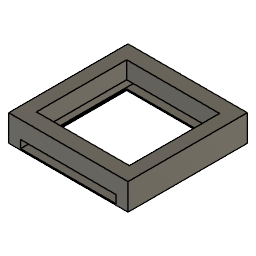
ELASTOMER HOUSING (Autodesk Fusion 360 design; units mm, degrees)
Autodesk Fusion 360 part; units mm, degrees
sketch "Sketch1" plane through (0, 0, 0) normal (0, 1, 0) x (1, 0, 0)
  line L0 (0, 0) -> (45, 0)
  line L1 (45, 0) -> (45, -10)
  line L2 (45, -10) -> (0, -10)
  line L3 (0, -10) -> (0, 0)
  line L4 (0, 0) -> (0, -2)
  line L5 (40.5, -3.5) -> (4.5, -3.5)
  line L6 (4.5, -3.5) -> (4.5, -0.5)
  line L7 (4.5, -0.5) -> (40.5, -0.5)
  line L8 (40.5, -0.5) -> (40.5, -3.5)
  dimension "d1" = 45
  dimension "d2" = 10
  dimension "d3" = 36
  dimension "d4" = 3
  constraint horizontal L0
  constraint vertical L1
  constraint horizontal L2
  constraint vertical L3
  constraint coincident L0.start L3.end
  constraint coincident L3 L4.end
  constraint horizontal L5
  constraint perpendicular L5 L6
  constraint parallel L5 L7
  constraint parallel L6 L8
  measures "d1" distance of L0.start L0.end
  measures "d2" distance of L0.start L2.end
  measures "d3" distance of L6.end L7.end
  measures "d4" distance of L5.end L6.end
extrude "Extrude1" add sketch "Sketch1" along normal blind 45
sketch "Sketch2" plane through (0, 0, 0.5) normal (0, 0, 1) x (-1, 0, 0)
  line L0 (-4.5, 0) -> (-40.5, 0)
  line L1 (-40.5, 0) -> (-40.5, -45)
  line L2 (-40.5, -45) -> (-4.5, -45)
  line L3 (-4.5, -45) -> (-4.5, 0)
  line L4 (-40, -44.5) -> (-5, -44.5)
  line L5 (-5, -44.5) -> (-5, -0.5)
  line L6 (-5, -0.5) -> (-40, -0.5)
  line L7 (-40, -0.5) -> (-40, -44.5)
  dimension "d7" = -0.5
extrude "Extrude2" cut sketch "Sketch2" against normal blind 8.5 contours L4 L5 L6 L7
extrude "Extrude3" add 1 faces at (28.3333, 44.5, 0.3333) along direction (0, -1, 0) blind 5
extrude "Extrude4" add 1 faces at (16.6667, 0.5, 0.3333) along direction (0, 1, 0) blind 5
sketch "Sketch3" plane through (0, 0, 0.5) normal (0, 0, 1) x (-1, 0, 0)
  line L0 (-40, -5.5) -> (-5, -5.5)
  line L1 (-5, -5.5) -> (-5, -39.5)
  line L2 (-5, -39.5) -> (-40, -39.5)
  line L3 (-40, -39.5) -> (-40, -5.5)
  constraint horizontal L0
  constraint vertical L1
  constraint horizontal L2
  constraint vertical L3
extrude "Extrude5" cut sketch "Sketch2" along normal blind 36 contours L4 L5 L6 L7
extrude "Extrude6" add 1 faces at (28.3333, 44.5, 5.6667) along direction (0, -1, 0) blind 6
extrude "Extrude7" add 1 faces at (16.6667, 0.5, 5.6667) along direction (0, 1, 0) blind 6
extrude "Extrude8" cut 1 faces at (28.3333, 38.5, 5.6667) along direction (0, 1, 0) blind 1
extrude "Extrude9" cut 1 faces at (16.6667, 6.5, 5.6667) along direction (0, -1, 0) blind 1
